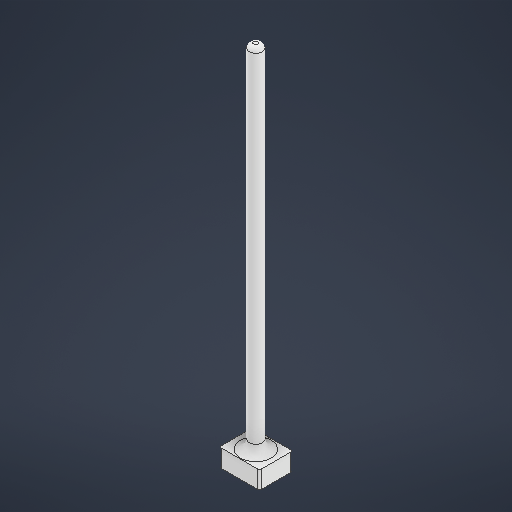
# Autodesk Inventor part: Концевик
Saved by Autodesk Inventor 2026 (Build 300175050, 175E)
## iProperties
Created: 2026-10-25
Part Number: Концевик
Material: Пластик АБС
Document SubType Name: Modeling
Designer: VK7
Density: 1.06 g/cm^3
Appearance: Гладкий — белый
Author: VK7
Autodesk Inventor part; units mm, degrees
ref_plane "YZ Plane" through (0, 0, 0) normal (1, 0, 0) x (0, 1, 0)
ref_plane "XZ Plane" through (0, 0, 0) normal (0, 1, 0) x (-1, 0, 0)
ref_plane "XY Plane" through (0, 0, 0) normal (0, 0, 1) x (1, 0, 0)
sketch "Эскиз2" plane through (0, 0, 0) normal (0, 1, 0) x (-1, 0, 0)
  line L0 (0.6222, 1.9335) -> (-0.5778, 1.9335)
  line L1 (-0.5778, 1.9335) -> (-0.5778, 0.5335)
  line L2 (-0.5778, 0.5335) -> (-1.9778, 0.5335)
  line L3 (-1.9778, 0.5335) -> (-1.9778, -0.6665)
  line L4 (-0.5778, -2.0665) -> (0.6222, -2.0665)
  line L5 (-1.9778, -0.6665) -> (-0.5778, -0.6665)
  line L6 (-0.5778, -0.6665) -> (-0.5778, -2.0665)
  line L7 (0.6222, -2.0665) -> (0.6222, -0.6665)
  line L8 (0.6222, -0.6665) -> (2.0222, -0.6665)
  line L9 (2.0222, -0.6665) -> (2.0222, 0.5335)
  line L10 (2.0222, 0.5335) -> (0.6222, 0.5335)
  line L11 (0.6222, 0.5335) -> (0.6222, 1.9335)
  line L12 (-3.5278, 2.6835) -> (-3.5278, -2.8165)
  line L13 (-1.6278, 2.6835) -> (-3.5278, 2.6835)
  line L14 (-3.1278, 2.2835) -> (-1.6278, 2.2835)
  line L15 (-1.6278, 2.2835) -> (-1.6278, 2.6835)
  line L16 (-3.1278, -2.4165) -> (-3.1278, 2.2835)
  line L17 (-1.6278, -2.4165) -> (-3.1278, -2.4165)
  line L18 (-1.6278, -2.8165) -> (-1.6278, -2.4165)
  line L19 (-3.5278, -2.8165) -> (-1.6278, -2.8165)
  line L20 (3.5722, 2.6835) -> (1.6722, 2.6835)
  line L21 (1.6722, 2.6835) -> (1.6722, 2.2835)
  line L22 (1.6722, 2.2835) -> (3.1722, 2.2835)
  line L23 (3.1722, 2.2835) -> (3.1722, -2.4165)
  line L24 (3.5722, -2.8165) -> (3.5722, 2.6835)
  line L25 (1.6722, -2.8165) -> (3.5722, -2.8165)
  line L26 (3.1722, -2.4165) -> (1.6722, -2.4165)
  line L27 (1.6722, -2.4165) -> (1.6722, -2.8165)
  line L28 (-3.5278, 2.6835) -> (-4.5278, 2.6835)
  line L29 (-4.5278, 2.6835) -> (-4.5278, 3.6835)
  line L30 (3.5722, -2.8165) -> (4.5722, -2.8165)
  line L31 (4.5722, -2.8165) -> (4.5722, -3.8165)
  line L32 (4.5722, -3.8165) -> (-4.5278, -3.8165)
  line L33 (-4.5278, -3.8165) -> (-4.5278, 3.6835)
  line L34 (-4.5278, 3.6835) -> (4.5722, 3.6835)
  line L35 (4.5722, 3.6835) -> (4.5722, -3.8165)
  point P0 (0, 0)
  dimension "d11" = 1
  dimension "d12" = 1
  dimension "d13" = 1
  dimension "d14" = 1
  constraints: 72 end point, 3 horizontal, 3 perpendicular, 2 parallel
  measures "d11" distance of L13.end L28.end
  measures "d12" distance of L28.end L29.end
  measures "d13" distance of L24.start L30.end
  measures "d14" distance of L30.end L31.end
extrude "Выдавливание1" add sketch "Эскиз2" along normal blind 3
sketch "Эскиз3" plane through (0, 3, 0) normal (0, 1, 0) x (1, 0, 0)
  line L0 (4.5278, 3.8165) -> (-4.5722, 3.8165) projected
  line L1 (-4.5722, -3.6835) -> (4.5278, -3.6835) projected
  line L2 (-4.5722, 3.8165) -> (4.5278, 3.8165)
  line L3 (4.5278, 3.8165) -> (4.5278, -3.6835)
  line L4 (4.5278, -3.6835) -> (-4.5722, -3.6835)
  line L5 (-4.5722, -3.6835) -> (-4.5722, 3.8165)
  point P0 (0, 0)
  constraints: 8 end point, 2 parallel, 1 horizontal, 1 perpendicular
extrude "Выдавливание2" add sketch "Эскиз3" along normal blind 1
sketch "Эскиз4" plane through (0, 4, 0) normal (0, 1, 0) x (1, 0, 0)
  circle A0 centre (0, 0) radius 1.5
  dimension "d19" = 3
  constraints: 1 centre point, 1 coincident
  measures "d19" diameter of A0
extrude "Выдавливание3" add sketch "Эскиз4" along normal blind 79.7
fillet "Сопряжение1" radius 2 1 edges at (-1.5, 4, 0)
fillet "Сопряжение2" radius 1 1 edges at (-1.5, 83.7, 0)
fillet "Сопряжение3" radius 0.5 4 edges at (-4.5722, 2, -3.8165) (-4.5722, 2, 3.6835) (4.5278, 2, -3.8165) (4.5278, 2, 3.6835)
